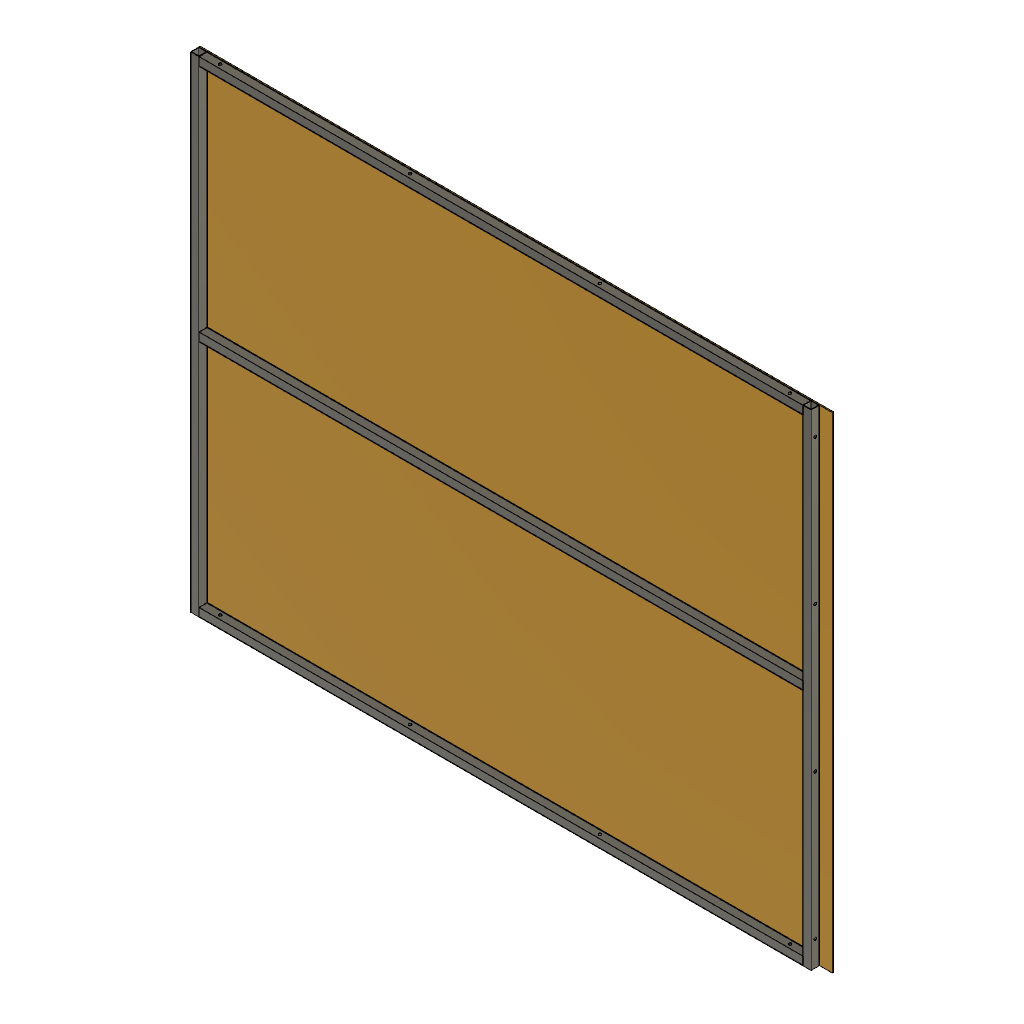
V2-SWL-00_P01_WALL-PANEL-ASSY-SIDE-LOWER-LH_CAD (Autodesk Fusion 360 design; units mm, degrees)
description: WALL - PANEL ASSY - SIDE LOWER - LH | Vách bên dưới - trái (cụm) | rev P01 | PROPOSED
part number: V2-SWL-00
description: WALL - PANEL FRAME - SIDE LOWER - LH | Khung vách bên dưới - trái | rev P01 | PROPOSED
part number: V2-SWL-10
description: WALL - FRAME STILE - REAR | Thanh đứng sau | rev P01 | PROPOSED
part number: V2-SWL-11
description: WALL - FRAME STILE - FRONT | Thanh đứng trước | rev P01 | PROPOSED
part number: V2-SWL-12
description: WALL - FRAME RAIL - BOTTOM | Thanh ngang dưới | rev P01 | PROPOSED
part number: V2-SWL-13
description: WALL - FRAME RAIL - TOP | Thanh ngang trên | rev P01 | PROPOSED
part number: V2-SWL-14
description: WALL - FRAME RAIL - MID | Thanh ngang giữa | rev P01 | PROPOSED
part number: V2-SWL-15
description: WALL - SKIN ACP 3 - SIDE LOWER - LH | Tấm ốp ACP 3 mm (VT01) | rev P01 | PROPOSED
part number: V2-SWL-20
Autodesk Fusion 360 part; units mm, degrees
sketch "SECTION - STILE FRONT TUBE" plane through (0, 0, 0) normal (0, 0, 1) x (1, 0, 0) in component "V2-SWL-12 WALL - FRAME STILE - FRONT"
  line L0 (0, 0) -> (20, 0)
  line L1 (20, 0) -> (20, -20)
  line L2 (20, -20) -> (0, -20)
  line L3 (0, -20) -> (0, 0)
  line L4 (1.2, -1.2) -> (18.8, -1.2)
  line L5 (18.8, -1.2) -> (18.8, -18.8)
  line L6 (18.8, -18.8) -> (1.2, -18.8)
  line L7 (1.2, -18.8) -> (1.2, -1.2)
  dimension "d19" = 20
  dimension "d20" = 20
  dimension "d21" = 1.2
  dimension "d22" = 1.2
  dimension "d23" = 17.6
  dimension "d24" = 17.6
  constraint horizontal L0
  constraint vertical L1
  constraint horizontal L2
  constraint vertical L3
  constraint horizontal L4
  constraint vertical L5
  constraint horizontal L6
  constraint vertical L7
  constraint coincident L0.start L3.end
  measures "d19" horizontal distance of L0.start L0.end
  measures "d20" vertical distance of L0.start L2.end
  measures "d21" horizontal distance of L0.start L4.start
  measures "d22" vertical distance of L0.start L4.start
  measures "d23" horizontal distance of L4.start L4.end
  measures "d24" vertical distance of L4.start L6.end
extrude "EXTRUDE - STILE FRONT TUBE" add sketch "SECTION - STILE FRONT TUBE" along normal blind 1150 makes body 1 in component "V2-SWL-12 WALL - FRAME STILE - FRONT"
sketch "SECTION - STILE REAR TUBE" plane through (0, 0, 0) normal (0, 0, 1) x (1, 0, 0) in component "V2-SWL-11 WALL - FRAME STILE - REAR"
  line L0 (1450, 0) -> (1470, 0)
  line L1 (1470, 0) -> (1470, -20)
  line L2 (1470, -20) -> (1450, -20)
  line L3 (1450, -20) -> (1450, 0)
  line L4 (1451.2, -1.2) -> (1468.8, -1.2)
  line L5 (1468.8, -1.2) -> (1468.8, -18.8)
  line L6 (1468.8, -18.8) -> (1451.2, -18.8)
  line L7 (1451.2, -18.8) -> (1451.2, -1.2)
  dimension "d27" = 20
  dimension "d28" = 20
  dimension "d29" = 1.2
  dimension "d30" = 1.2
  dimension "d31" = 17.6
  dimension "d32" = 17.6
  dimension "d33" = 1450
  constraint horizontal L0
  constraint vertical L1
  constraint horizontal L2
  constraint vertical L3
  constraint horizontal L4
  constraint vertical L5
  constraint horizontal L6
  constraint vertical L7
  constraint horizontal origin L0.start
  measures "d27" horizontal distance of L0.start L0.end
  measures "d28" vertical distance of L0.start L2.end
  measures "d29" horizontal distance of L0.start L4.start
  measures "d30" vertical distance of L0.start L4.start
  measures "d31" horizontal distance of L4.start L4.end
  measures "d32" vertical distance of L4.start L6.end
  measures "d33" horizontal distance of origin L0.start
extrude "EXTRUDE - STILE REAR TUBE" add sketch "SECTION - STILE REAR TUBE" along normal blind 1150 separate body makes body 2 in component "V2-SWL-11 WALL - FRAME STILE - REAR"
sketch "SECTION - RAIL BOTTOM TUBE" plane through (0, 0, 0) normal (1, 0, 0) x (0, 0, -1) in component "V2-SWL-13 WALL - FRAME RAIL - BOTTOM"
  line L0 (0, 0) -> (-20, 0)
  line L1 (-20, 0) -> (-20, -20)
  line L2 (-20, -20) -> (0, -20)
  line L3 (0, -20) -> (0, 0)
  line L4 (-1.2, -1.2) -> (-18.8, -1.2)
  line L5 (-18.8, -1.2) -> (-18.8, -18.8)
  line L6 (-18.8, -18.8) -> (-1.2, -18.8)
  line L7 (-1.2, -18.8) -> (-1.2, -1.2)
  dimension "d36" = 20
  dimension "d37" = 20
  dimension "d38" = 1.2
  dimension "d39" = 1.2
  dimension "d40" = 17.6
  dimension "d41" = 17.6
  constraint horizontal L0
  constraint vertical L1
  constraint horizontal L2
  constraint vertical L3
  constraint horizontal L4
  constraint vertical L5
  constraint horizontal L6
  constraint vertical L7
  constraint coincident L0.start L3.end
  measures "d36" vertical distance of L0.start L2.end
  measures "d37" horizontal distance of L0.start L0.end
  measures "d38" vertical distance of L0.start L4.start
  measures "d39" horizontal distance of L0.start L4.start
  measures "d40" vertical distance of L4.start L6.end
  measures "d41" horizontal distance of L4.start L4.end
extrude "EXTRUDE - RAIL BOTTOM TUBE" add sketch "SECTION - RAIL BOTTOM TUBE" along normal blind 1430 from surface at 20 separate body makes body 3 in component "V2-SWL-13 WALL - FRAME RAIL - BOTTOM"
sketch "SECTION - RAIL TOP TUBE" plane through (0, 0, 0) normal (1, 0, 0) x (0, 0, -1) in component "V2-SWL-14 WALL - FRAME RAIL - TOP"
  line L0 (-1130, 0) -> (-1150, 0)
  line L1 (-1150, 0) -> (-1150, -20)
  line L2 (-1150, -20) -> (-1130, -20)
  line L3 (-1130, -20) -> (-1130, 0)
  line L4 (-1131.2, -1.2) -> (-1148.8, -1.2)
  line L5 (-1148.8, -1.2) -> (-1148.8, -18.8)
  line L6 (-1148.8, -18.8) -> (-1131.2, -18.8)
  line L7 (-1131.2, -18.8) -> (-1131.2, -1.2)
  dimension "d45" = 20
  dimension "d46" = 20
  dimension "d47" = 1.2
  dimension "d48" = 1.2
  dimension "d49" = 17.6
  dimension "d50" = 17.6
  dimension "d51" = 1130
  constraint horizontal L0
  constraint vertical L1
  constraint horizontal L2
  constraint vertical L3
  constraint horizontal L4
  constraint vertical L5
  constraint horizontal L6
  constraint vertical L7
  constraint horizontal origin L0.start
  measures "d45" vertical distance of L0.start L2.end
  measures "d46" horizontal distance of L0.start L0.end
  measures "d47" vertical distance of L0.start L4.start
  measures "d48" horizontal distance of L0.start L4.start
  measures "d49" vertical distance of L4.start L6.end
  measures "d50" horizontal distance of L4.start L4.end
  measures "d51" horizontal distance of origin L0.start
extrude "EXTRUDE - RAIL TOP TUBE" add sketch "SECTION - RAIL TOP TUBE" along normal blind 1430 from surface at 20 separate body makes body 4 in component "V2-SWL-14 WALL - FRAME RAIL - TOP"
sketch "SECTION - RAIL MID TUBE" plane through (0, 0, 0) normal (1, 0, 0) x (0, 0, -1) in component "V2-SWL-15 WALL - FRAME RAIL - MID"
  line L0 (-565, 0) -> (-585, 0)
  line L1 (-585, 0) -> (-585, -20)
  line L2 (-585, -20) -> (-565, -20)
  line L3 (-565, -20) -> (-565, 0)
  line L4 (-566.2, -1.2) -> (-583.8, -1.2)
  line L5 (-583.8, -1.2) -> (-583.8, -18.8)
  line L6 (-583.8, -18.8) -> (-566.2, -18.8)
  line L7 (-566.2, -18.8) -> (-566.2, -1.2)
  dimension "d55" = 20
  dimension "d56" = 20
  dimension "d57" = 1.2
  dimension "d58" = 1.2
  dimension "d59" = 17.6
  dimension "d60" = 17.6
  dimension "d61" = 565
  constraint horizontal L0
  constraint vertical L1
  constraint horizontal L2
  constraint vertical L3
  constraint horizontal L4
  constraint vertical L5
  constraint horizontal L6
  constraint vertical L7
  constraint horizontal origin L0.start
  measures "d55" vertical distance of L0.start L2.end
  measures "d56" horizontal distance of L0.start L0.end
  measures "d57" vertical distance of L0.start L4.start
  measures "d58" horizontal distance of L0.start L4.start
  measures "d59" vertical distance of L4.start L6.end
  measures "d60" horizontal distance of L4.start L4.end
  measures "d61" horizontal distance of origin L0.start
extrude "EXTRUDE - RAIL MID TUBE" add sketch "SECTION - RAIL MID TUBE" along normal blind 1430 from surface at 20 separate body makes body 5 in component "V2-SWL-15 WALL - FRAME RAIL - MID"
ref_plane "WorkPlane1" through (0, 0, 1150) normal (0, 0, 1) x (1, 0, 0) in component "V2-SWL-14 WALL - FRAME RAIL - TOP"
sketch "HOLE POSITION - TOP RAIL TO UPPER FRAME" plane through (0, 0, 1150) normal (0, 0, 1) x (1, 0, 0) in component "V2-SWL-14 WALL - FRAME RAIL - TOP"
  point P0 (60, -10)
  dimension "d67" = 60
  dimension "d68" = 10
  measures "d67" horizontal distance of origin P0
  measures "d68" vertical distance of origin P0
hole "HOLE - M6 CLEARANCE - TOP RAIL TO UPPER FRAME" at (60, -10, 1150) direction (0, 0, -1) diameter 6.6 depth 20 tip angle 118 bodies 4 in component "V2-SWL-14 WALL - FRAME RAIL - TOP"
pattern_linear "PATTERN - TOP RAIL TO UPPER FRAME HOLES" count 4 spacing 450 along (1, 0, 0) count 3 spacing 0 along (1, 0, 0) of "HOLE - M6 CLEARANCE - TOP RAIL TO UPPER FRAME" in component "V2-SWL-14 WALL - FRAME RAIL - TOP"
ref_plane "WorkPlane1" through (0, 0, 20) normal (0, 0, 1) x (1, 0, 0) in component "V2-SWL-13 WALL - FRAME RAIL - BOTTOM"
sketch "HOLE POSITION - BOTTOM RAIL TO BASE" plane through (0, 0, 20) normal (0, 0, 1) x (1, 0, 0) in component "V2-SWL-13 WALL - FRAME RAIL - BOTTOM"
  point P0 (60, -10)
  dimension "d78" = 60
  dimension "d79" = 10
  measures "d78" horizontal distance of origin P0
  measures "d79" vertical distance of origin P0
hole "HOLE - M6 CLEARANCE - BOTTOM RAIL TO BASE" at (60, -10, 20) direction (0, 0, -1) diameter 6.6 depth 20 tip angle 118 bodies 3 in component "V2-SWL-13 WALL - FRAME RAIL - BOTTOM"
pattern_linear "PATTERN - BOTTOM RAIL TO BASE HOLES" count 4 spacing 450 along (1, 0, 0) count 3 spacing 0 along (1, 0, 0) of "HOLE - M6 CLEARANCE - BOTTOM RAIL TO BASE" in component "V2-SWL-13 WALL - FRAME RAIL - BOTTOM"
ref_plane "WorkPlane1" through (1450, 0, 0) normal (1, 0, 0) x (0, 1, 0) in component "V2-SWL-11 WALL - FRAME STILE - REAR"
sketch "HOLE POSITION - REAR STILE TO BACK WALL" plane through (1450, 0, 0) normal (1, 0, 0) x (0, 0, -1) in component "V2-SWL-11 WALL - FRAME STILE - REAR"
  point P0 (-60, -10)
  dimension "d89" = 10
  dimension "d90" = 60
  measures "d89" vertical distance of origin P0
  measures "d90" horizontal distance of origin P0
hole "HOLE - M6 CLEARANCE - REAR STILE TO BACK WALL" at (1450, -10, 60) direction (1, 0, 0) diameter 6.6 depth 20 tip angle 118 bodies 2 in component "V2-SWL-11 WALL - FRAME STILE - REAR"
pattern_linear "PATTERN - REAR STILE TO BACK WALL HOLES" count 4 spacing 343.3333 along (0, 0, 1) count 3 spacing 0 along (0, 0, 1) of "HOLE - M6 CLEARANCE - REAR STILE TO BACK WALL" in component "V2-SWL-11 WALL - FRAME STILE - REAR"
sketch "OUTLINE - ACP SKIN" plane through (0, 0, 0) normal (0, 1, 0) x (1, 0, 0) in component "V2-SWL-20 WALL - SKIN ACP 3 - SIDE LOWER - LH"
  line L0 (0, 0) -> (1500, 0)
  line L1 (1500, 0) -> (1500, -1150)
  line L2 (1500, -1150) -> (0, -1150)
  line L3 (0, -1150) -> (0, 0)
  dimension "d98" = 1500
  dimension "d99" = 1150
  constraint horizontal L0
  constraint vertical L1
  constraint horizontal L2
  constraint vertical L3
  constraint coincident L0.start L3.end
  measures "d98" horizontal distance of L0.start L0.end
  measures "d99" vertical distance of L0.start L2.end
extrude "EXTRUDE - ACP SKIN" add sketch "OUTLINE - ACP SKIN" along normal blind 3 separate body makes body 6 in component "V2-SWL-20 WALL - SKIN ACP 3 - SIDE LOWER - LH"
component "V2-SWL-10 WALL - PANEL FRAME - SIDE LOWER - LH" placed x (1, 0, 0) y (0, 1, 0) z (0, 0, 1) at (0, 0, 0)
component "V2-SWL-20 WALL - SKIN ACP 3 - SIDE LOWER - LH" placed x (1, 0, 0) y (0, 1, 0) z (0, 0, 1) at (0, 0, 0)
component "V2-SWL-11 WALL - FRAME STILE - REAR" placed x (1, 0, 0) y (0, 1, 0) z (0, 0, 1) at (0, 0, 0) in component "V2-SWL-10 WALL - PANEL FRAME - SIDE LOWER - LH"
component "V2-SWL-12 WALL - FRAME STILE - FRONT" placed x (1, 0, 0) y (0, 1, 0) z (0, 0, 1) at (0, 0, 0) in component "V2-SWL-10 WALL - PANEL FRAME - SIDE LOWER - LH"
component "V2-SWL-13 WALL - FRAME RAIL - BOTTOM" placed x (1, 0, 0) y (0, 1, 0) z (0, 0, 1) at (0, 0, 0) in component "V2-SWL-10 WALL - PANEL FRAME - SIDE LOWER - LH"
component "V2-SWL-14 WALL - FRAME RAIL - TOP" placed x (1, 0, 0) y (0, 1, 0) z (0, 0, 1) at (0, 0, 0) in component "V2-SWL-10 WALL - PANEL FRAME - SIDE LOWER - LH"
component "V2-SWL-15 WALL - FRAME RAIL - MID" placed x (1, 0, 0) y (0, 1, 0) z (0, 0, 1) at (0, 0, 0) in component "V2-SWL-10 WALL - PANEL FRAME - SIDE LOWER - LH"
equation "frame_width = 1470 mm" comment "Frame outer width along X. CALCULATION: side wall depth 1500 (SOURCE: build plan II) - rear skin overhang 30."
equation "frame_height = 1150 mm" comment "Frame outer height along Z. CALCULATION: wall height 2300 (SOURCE: v1 BOM, walls 2300 tall) / 2 frames (SOURCE: build plan II). HOLD: a thin floor would make walls about 80 taller."
equation "tube_size = 20 mm" comment "Square tube outside size. SOURCE: build plan VT10, box section 20x20."
equation "tube_wall = 1.2 mm" comment "Tube wall thickness. ASSUMPTION: plan gives none; 1.2 is a common 20x20 steel wall (about 1.5 for aluminium). UNVERIFIED with a supplier."
equation "frame_material = 'Steel'" comment "Tube material, 'Steel' (SOURCE: build plan VT10) or 'Aluminum' (PROPOSED in v2 plan). The build script maps it to a Fusion material."
equation "hole_dia = 6.6 mm" comment "Joint hole for an M6 bolt. SOURCE: ISO 273 medium clearance for M6 = 6.6. Bolt M6x60 (SOURCE: build plan VT11)."
equation "hole_edge_dist = 60 mm" comment "First and last hole centre from the frame outer edge. ASSUMPTION: stile 20 + weld 3 + washer radius 6 + wrench swing 25 = 54, rounded up. Check in the joint register."
equation "rail_hole_pitch_max = 500 mm" comment "Largest pitch allowed between rail holes. ASSUMPTION until the joint and gasket calculation (J-WALL-01) sets it."
equation "rail_hole_count = ceil(( frame_width - 2 * hole_edge_dist ) / rail_hole_pitch_max) + 1" comment "CALCULATION: holes per rail, equal pitch, first and last at hole_edge_dist."
equation "rail_hole_pitch = ( frame_width - 2 * hole_edge_dist ) / ( rail_hole_count - 1 )" comment "CALCULATION: actual pitch of the rail holes."
equation "stile_hole_pitch_max = 400 mm" comment "Largest pitch allowed between rear stile holes. ASSUMPTION until J-WALL-02."
equation "stile_hole_count = ceil(( frame_height - 2 * hole_edge_dist ) / stile_hole_pitch_max) + 1" comment "CALCULATION: holes in the rear stile, equal pitch."
equation "stile_hole_pitch = ( frame_height - 2 * hole_edge_dist ) / ( stile_hole_count - 1 )" comment "CALCULATION: actual pitch of the rear stile holes."
equation "mid_rail_z = frame_height / 2" comment "Height of the mid rail centre line. ASSUMPTION: halves the unsupported skin span."
equation "skin_thk = 3 mm" comment "ACP skin thickness. SOURCE: build plan VT01, ACP 3 mm, Dark Yellow EV3038."
equation "skin_overhang_rear = 30 mm" comment "Skin runs past the frame rear edge to cover the back wall edge. SOURCE: build plan joint detail, ACP 3 + ply 6 + frame 20 + gap 1."
equation "skin_width = frame_width + skin_overhang_rear" comment "CALCULATION: equals the side wall depth 1500."
equation "skin_height = frame_height" comment "ASSUMPTION: skin flush with the frame top and bottom. HOLD: seam gap to the upper panel."
equation "d19 = tube_size"
equation "d20 = tube_size"
equation "d21 = tube_wall"
equation "d22 = tube_wall"
equation "d23 = tube_size - 2 * tube_wall"
equation "d24 = tube_size - 2 * tube_wall"
equation "d25 = frame_height"
equation "d27 = tube_size"
equation "d28 = tube_size"
equation "d29 = tube_wall"
equation "d30 = tube_wall"
equation "d31 = tube_size - 2 * tube_wall"
equation "d32 = tube_size - 2 * tube_wall"
equation "d33 = frame_width - tube_size"
equation "d34 = frame_height"
equation "d36 = tube_size"
equation "d37 = tube_size"
equation "d38 = tube_wall"
equation "d39 = tube_wall"
equation "d40 = tube_size - 2 * tube_wall"
equation "d41 = tube_size - 2 * tube_wall"
equation "d42 = tube_size"
equation "d43 = frame_width - 2 * tube_size"
equation "d45 = tube_size"
equation "d46 = tube_size"
equation "d47 = tube_wall"
equation "d48 = tube_wall"
equation "d49 = tube_size - 2 * tube_wall"
equation "d50 = tube_size - 2 * tube_wall"
equation "d51 = frame_height - tube_size"
equation "d52 = tube_size"
equation "d53 = frame_width - 2 * tube_size"
equation "d55 = tube_size"
equation "d56 = tube_size"
equation "d57 = tube_wall"
equation "d58 = tube_wall"
equation "d59 = tube_size - 2 * tube_wall"
equation "d60 = tube_size - 2 * tube_wall"
equation "d61 = mid_rail_z - tube_size / 2"
equation "d62 = tube_size"
equation "d63 = frame_width - 2 * tube_size"
equation "d65 = frame_height"
equation "d67 = hole_edge_dist"
equation "d68 = tube_size / 2"
equation "d69 = tube_size"
equation "d70 = hole_dia"
equation "d72 = rail_hole_count"
equation "d74 = frame_width - 2 * hole_edge_dist"
equation "d76 = tube_size"
equation "d78 = hole_edge_dist"
equation "d79 = tube_size / 2"
equation "d80 = tube_size"
equation "d81 = hole_dia"
equation "d83 = rail_hole_count"
equation "d85 = frame_width - 2 * hole_edge_dist"
equation "d87 = frame_width - tube_size"
equation "d89 = tube_size / 2"
equation "d90 = hole_edge_dist"
equation "d91 = tube_size"
equation "d92 = hole_dia"
equation "d94 = stile_hole_count"
equation "d96 = frame_height - 2 * hole_edge_dist"
equation "d98 = skin_width"
equation "d99 = skin_height"
equation "d100 = skin_thk"
named bodies: "WALL - FRAME STILE - FRONT - TUBE", "WALL - FRAME STILE - REAR - TUBE", "WALL - FRAME RAIL - BOTTOM - TUBE", "WALL - FRAME RAIL - TOP - TUBE", "WALL - FRAME RAIL - MID - TUBE", "WALL - SKIN ACP 3 - SIDE LOWER - LH - SHEET"
